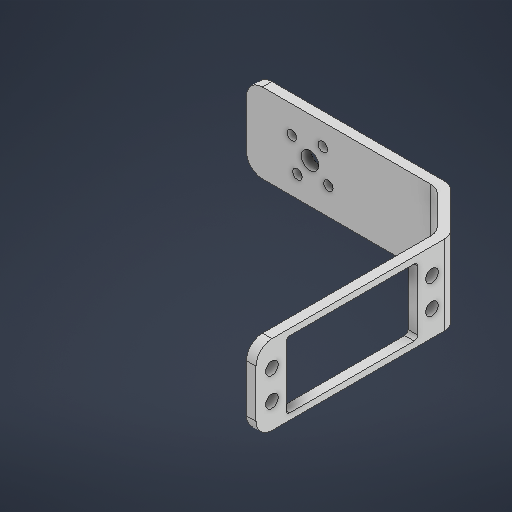
# Autodesk Inventor part: Base_Z
Saved by Autodesk Inventor 2027 (Build 310192060, 192F)
## iProperties
Created: 2026-09-18
Part Number: Base_Z
Material: Genérico
Document SubType Name: Modeling
Designer: Bolivar A.
Density: 1 g/cm^3
Appearance: Valor por defecto
Project: STAR TRACKER
Author: Bolivar A.
Title: Soporte lateral
Autodesk Inventor part; units mm, degrees
ref_plane "YZ Plane" through (0, 0, 0) normal (1, 0, 0) x (0, 1, 0)
ref_plane "XZ Plane" through (0, 0, 0) normal (0, 1, 0) x (-1, 0, 0)
ref_plane "XY Plane" through (0, 0, 0) normal (0, 0, 1) x (1, 0, 0)
sketch "Boceto1" plane through (0, 0, 0) normal (0, 0, 1) x (1, 0, 0)
  line L0 (-30, 12.5) -> (30, 12.5)
  line L1 (30, 12.5) -> (30, -12.5)
  line L2 (30, -12.5) -> (-30, -12.5)
  line L3 (-30, -12.5) -> (-30, 12.5)
  point P0 (0, 0)
  point P1 (-30, 0)
  point P2 (0, -12.5)
  dimension "d0" = 60
  dimension "d1" = 25
  constraints: 8 end point, 2 midpoint, 2 parallel, 1 horizontal, 1 horizontal alignment, 1 perpendicular, 1 vertical alignment
  measures "d0" distance of L1.end L2.end
  measures "d1" distance of L0.end L1.end
extrude "Extrusión1" add sketch "Boceto1" along normal blind 3
sketch "Boceto2" plane through (-30, 12.5, 0) normal (0, 1, 0) x (1, 0, 0)
  line L0 (60, 0) -> (0, 0) projected
  line L1 (0, 0) -> (0, -3) projected
  line L2 (60, -3) -> (0, -3) projected
  line L3 (60, 0) -> (60, -3) projected
  line L4 (75, -75) -> (72, -75)
  line L5 (72, -75) -> (72, -15)
  line L6 (72, -15) -> (75, -15)
  line L7 (75, -15) -> (75, -75)
  line L8 (60, 0) -> (75, 0)
  line L9 (75, 0) -> (75, -15)
  line L10 (72, -15) -> (60, -3)
  line L11 (68.1213, -6.8787) -> (66, -9)
  line L12 (75, -13.7574) -> (61.2426, 0)
  line L13 (0, 0) -> (0, -3) projected
  line L14 (60, 0) -> (60, -3) projected
  line L15 (60, -3) -> (0, -3) projected
  point P0 (30, 0)
  dimension "d6" = 15
  dimension "d7" = 15
  constraints: 18 end point, 3 equal length, 3 perpendicular, 2 horizontal, 2 midpoint, 2 parallel, 2 point on line, 1 vertical
  measures "d6" distance of L0.start L8.end
  measures "d7" distance of L8.end L6.end
extrude "Extrusión2" add sketch "Boceto2" against normal blind 25 contours L8 L12 L11 L10 L3 | L11 L12 L9 L6 L10 | L6 L7 L4 L5
fillet "Empalme1" radius 5 4 edges at (43.5, 12.5, 75) (43.5, -12.5, 75) (-30, 12.5, 1.5) (-30, -12.5, 1.5)
fillet "Empalme2" radius 5 4 edges at (45, 0, 13.7574) (30, 0, 3) (42, 0, 15) (31.2426, 0, 0)
sketch "Boceto3" plane through (0, 0, 3) normal (0, 0, 1) x (1, 0, 0)
  circle A0 centre (-10, 0) radius 2.75 projected
  circle A1 centre (-10, 0) radius 10 projected
  circle A2 centre (-4.2484, -3.9899) radius 1.5 projected
  circle A3 centre (-13.9899, -5.7516) radius 1.5 projected
  circle A4 centre (-15.7516, 3.9899) radius 1.5 projected
  circle A5 centre (-6.0101, 5.7516) radius 1.5 projected
  point P0 (0, 0)
  constraints: 1 horizontal alignment
extrude "Extrusión3" cut sketch "Boceto3" against normal blind 3 contours A0 | A2 | A3 | A4 | A5
sketch "Boceto4" plane through (42, -7.5, 75) normal (-1, 0, 0) x (0, 0, 1)
  arc A0 (-3.95, 13.956) -> (-3.95, 10.044) centre (-5, 12) ccw projected
  arc A1 (-3.95, 4.956) -> (-3.95, 1.044) centre (-5, 3) ccw projected
  arc A2 (-56.35, 10.044) -> (-56.35, 13.956) centre (-55.3, 12) ccw projected
  arc A3 (-56.35, 1.044) -> (-56.35, 4.956) centre (-55.3, 3) ccw projected
  line L0 (-20, -2.5) -> (-44.1422, -2.5) projected
  line L1 (-10.6, -2.5) -> (-20, -2.5) projected
  arc A4 (-10.6, -2.5) -> (-10, -1.9) centre (-10.6, -1.9) ccw projected
  line L2 (-10, 4.0883) -> (-10, -1.9) projected
  line L3 (-10, 7.5) -> (-10, 4.0883) projected
  line L4 (-10, 10.9117) -> (-10, 7.5) projected
  line L5 (-10, 16.9) -> (-10, 10.9117) projected
  arc A5 (-10, 16.9) -> (-10.6, 17.5) centre (-10.6, 16.9) ccw projected
  line L6 (-20, 17.5) -> (-10.6, 17.5) projected
  line L7 (-44.1422, 17.5) -> (-20, 17.5) projected
  line L8 (-49.7, 17.5) -> (-44.1422, 17.5) projected
  arc A6 (-49.7, 17.5) -> (-50.3, 16.9) centre (-49.7, 16.9) ccw projected
  line L9 (-50.3, -1.9) -> (-50.3, 16.9) projected
  arc A7 (-50.3, -1.9) -> (-49.7, -2.5) centre (-49.7, -1.9) ccw projected
  line L10 (-44.1422, -2.5) -> (-49.7, -2.5) projected
  arc A8 (-9.5, 16.9) -> (-10.6, 18) centre (-10.6, 16.9) ccw
  line L11 (-9.5, 16.9) -> (-9.5, 10.9117)
  line L12 (-9.5, 10.9117) -> (-9.5, 7.5)
  line L13 (-9.5, 7.5) -> (-9.5, 4.0883)
  line L14 (-9.5, 4.0883) -> (-9.5, -1.9)
  arc A9 (-10.6, -3) -> (-9.5, -1.9) centre (-10.6, -1.9) ccw
  line L15 (-10.6, -3) -> (-20, -3)
  line L16 (-20, -3) -> (-44.1422, -3)
  line L17 (-44.1422, -3) -> (-49.7, -3)
  arc A10 (-50.8, -1.9) -> (-49.7, -3) centre (-49.7, -1.9) ccw
  line L18 (-50.8, -1.9) -> (-50.8, 16.9)
  arc A11 (-49.7, 18) -> (-50.8, 16.9) centre (-49.7, 16.9) ccw
  line L19 (-49.7, 18) -> (-44.1422, 18)
  line L20 (-44.1422, 18) -> (-20, 18)
  line L21 (-20, 18) -> (-10.6, 18)
  circle A12 centre (-5, 12) radius 2
  circle A13 centre (-5, 3) radius 2
  circle A14 centre (-55.3, 12) radius 2
  circle A15 centre (-55.3, 3) radius 2
  point P0 (-75, 7.5)
  dimension "d15" = 0.5
  dimension "d16" = 4
  constraints: 22 end point, 8 centre point, 8 point on circle, 4 coincident, 3 equal radius, 14 other
  measures "d15" distance between parallel lines of L6 L21
  measures "d16" diameter of A12
extrude "Extrusión4" cut sketch "Boceto4" against normal blind 3 contours L0 L10 A7 L9 A6 L8 L7 L6 A5 L5 L4 L3 L2 A4 L1 | L11 L12 L13 L14 A9 L15 L16 L17 A10 L18 A11 L19 L20 L21 A8 | A12 | A13 | A14 | A15
